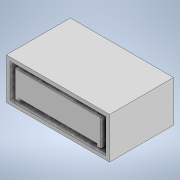
# Autodesk Inventor part: dulap_NOPTIERA
Saved by Autodesk Inventor 2022.6 (Build 266554000, 554)
## iProperties
Created: 2025-04-13
Part Number: dulap_NOPTIERA
Material: Generic
Document SubType Name: Modeling
Designer: Dragos Macovei
Density: 1 g/cm^3
Appearance: Default
Author: Dragos Macovei
Autodesk Inventor part; units mm, degrees
ref_plane "YZ Plane" through (0, 0, 0) normal (1, 0, 0) x (0, 1, 0)
ref_plane "XZ Plane" through (0, 0, 0) normal (0, 1, 0) x (-1, 0, 0)
ref_plane "XY Plane" through (0, 0, 0) normal (0, 0, 1) x (1, 0, 0)
sketch "Sketch1" plane through (0, 0, 0) normal (0, 0, 1) x (1, 0, 0)
  line L0 (0, 0) -> (-464, 0)
  line L1 (-464, 0) -> (-464, 164)
  line L2 (-464, 164) -> (0, 164)
  line L3 (0, 164) -> (0, 0)
  line L4 (-482, 182) -> (18, 182)
  line L5 (18, 182) -> (18, -18)
  line L6 (18, -18) -> (-482, -18)
  line L7 (-482, -18) -> (-482, 182)
  dimension "d2" = 18
  dimension "d3" = 18
  dimension "d4" = 18
  dimension "d5" = 18
  dimension "d15" = 500
  dimension "d16" = 200
  constraints: 16 end point, 4 parallel, 2 horizontal, 2 perpendicular
  measures "d2" distance between parallel lines of L5 L3
  measures "d3" distance between parallel lines of L2 L4
  measures "d4" distance between parallel lines of L7 L1
  measures "d5" distance between parallel lines of L6 L0
  measures "d15" distance between parallel lines of L5 L7
  measures "d16" distance between parallel lines of L6 L4
extrude "Extrusion1" add sketch "Sketch1" against normal blind 310
sketch "Sketch2" plane through (0, 0, 0) normal (0, 0, 1) x (1, 0, 0)
  line L0 (-482, -18) -> (18, -18) projected
  line L1 (18, -18) -> (18, 182) projected
  line L2 (18, 182) -> (-482, 182) projected
  line L3 (-482, 182) -> (-482, -18) projected
  line L4 (0, 0) -> (-464, 0) projected
  line L5 (-464, 0) -> (-464, 164) projected
  line L6 (-464, 164) -> (0, 164) projected
  line L7 (0, 164) -> (0, 0) projected
  line L8 (-439.5, 148) -> (-421.5, 148)
  line L9 (-24.5, 148) -> (-24.5, 30)
  line L10 (-24.5, 30) -> (-439.5, 30)
  line L11 (-439.5, 30) -> (-439.5, 148)
  line L12 (0, 164) -> (-464, 164) construction
  line L13 (-232, 164) -> (-232, 0) construction
  line L14 (-42.5, 65.9374) -> (-42.5, 48)
  line L15 (-42.5, 48) -> (-421.5, 48)
  line L16 (-421.5, 48) -> (-421.5, 101.6702)
  line L17 (-421.5, 101.6702) -> (-421.5, 148)
  line L18 (-42.5, 65.9374) -> (-42.5, 148)
  line L19 (-42.5, 148) -> (-24.5, 148)
  line L20 (-439.5, 30) -> (-421.5, 30)
  line L21 (-421.5, 30) -> (-421.5, 18)
  line L22 (-421.5, 18) -> (-439.5, 18)
  line L23 (-439.5, 18) -> (-439.5, 30)
  line L24 (-24.5, 30) -> (-42.5, 30)
  line L25 (-42.5, 30) -> (-42.5, 18)
  line L26 (-42.5, 18) -> (-24.5, 18)
  line L27 (-24.5, 18) -> (-24.5, 30)
  point P0 (-24.5, 89)
  dimension "d8" = 415
  dimension "d9" = 464
  dimension "d10" = 18
  dimension "d11" = 18
  dimension "d12" = 18
  dimension "d17" = 30
  dimension "d18" = 12
  dimension "d19" = 100
  dimension "d20" = 100
  constraints: 38 end point, 7 parallel, 4 perpendicular, 3 horizontal, 3 midpoint, 2 point on line, 2 vertical
  measures "d8" distance between parallel lines of L9 L11
  measures "d9" distance of L5.end L6.end
  measures "d10" distance between parallel lines of L11 L16
  measures "d11" distance between parallel lines of L10 L15
  measures "d12" distance from line of point (-24.5, 89) L14
  measures "d17" distance between parallel lines of L4 L10
  measures "d18" distance of L26.end L9.end
  measures "d19" distance of L8.end L15.end
  measures "d20" distance of L18.end L14.end
extrude "Extrusion2" add sketch "Sketch2" against normal blind 300 contours L8 L17 L16 L15 L14 L18 L19 L9 L10 L11 | L10 L21 L22 L23 | L10 L27 L26 L25
sketch "Sketch4" plane through (-42.5, 48, 0) normal (-1, 0, 0) x (0, 0, 1)
  line L0 (0, -30) -> (0, 100) projected
  line L1 (0, -30) -> (-300, -30) projected
  line L2 (-300, 100) -> (-300, -30) projected
  line L3 (0, 100) -> (-300, 100) projected
  line L4 (-300, 100) -> (-300, -30) projected
  line L5 (0, -30) -> (-300, -30) projected
  line L6 (-300, 100) -> (-282, 100)
  line L7 (-282, 100) -> (-282, -30)
  line L8 (-282, -30) -> (-300, -30)
  line L9 (-300, -30) -> (-300, 100)
  line L10 (0, 100) -> (-18, 100)
  line L11 (-18, 100) -> (-18, -30)
  line L12 (-18, -30) -> (0, -30)
  line L13 (0, -30) -> (0, 100)
  line L14 (0, 0) -> (-300, 0) projected
  line L15 (0, 0) -> (-300, 0) projected
  line L16 (0, 0) -> (-300, 0) projected
  line L17 (-300, 0) -> (0, 0)
  point P0 (0, -48)
  point P1 (-18, 0)
  point P2 (-282, 0)
  dimension "d21" = 18
  dimension "d22" = 18
  constraints: 18 end point, 4 parallel, 3 horizontal, 2 perpendicular, 2 point on line
  measures "d21" distance between parallel lines of L0 L11
  measures "d22" distance between parallel lines of L2 L7
extrude "Extrusion3" add sketch "Sketch4" along normal up to surface (379 mm away) contours L14 L11 L3 L0 | L14 L2 L3 L7
body "Solid1"
